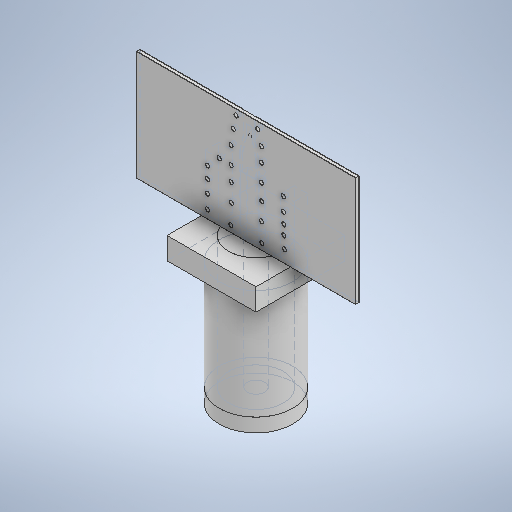
# Autodesk Inventor part: 06_coonector_plus_02mm_res
Saved by Autodesk Inventor 2025.3 (Build 293356000, 356)
## iProperties
Created: 2026-10-17
Part Number: 06_coonector_plus_02mm_res
Material: Generisch
Document SubType Name: Modeling
Designer: v.ivko
Density: 1 g/cm^3
Appearance: Vorgabe
Author: v.ivko
Autodesk Inventor part; units mm, degrees
ref_plane "YZ Plane" through (0, 0, 0) normal (1, 0, 0) x (0, 1, 0)
ref_plane "XZ Plane" through (0, 0, 0) normal (0, 1, 0) x (-1, 0, 0)
ref_plane "XY Plane" through (0, 0, 0) normal (0, 0, 1) x (1, 0, 0)
sketch "Skizze1" plane through (0, 0, 0) normal (0, 0, 1) x (1, 0, 0)
  line L0 (-8, -4) -> (8, -4)
  line L1 (8, -4) -> (8, 4)
  line L2 (8, 4) -> (-8, 4)
  line L3 (-8, 4) -> (-8, -4)
  line L4 (-8, -4) -> (8, 4) construction
  line L5 (8, -4) -> (-8, 4) construction
  point P0 (0, 0)
  dimension "d39" = 16
  dimension "d42" = 8
  constraints: 12 end point, 2 midpoint, 2 parallel, 1 horizontal, 1 perpendicular
  measures "d39" distance between parallel lines of L1 L3
  measures "d42" distance of L0.end L1.end
extrude "Extrusion1" add sketch "Skizze1" along normal blind 0.2
sketch "Skizze2" plane through (-8, -4, 0) normal (0, -1, 0) x (1, 0, 0)
  line L0 (8, 0) -> (8, -43.5363) construction
  line L1 (11.25, 2.75) -> (4.75, 2.75)
  line L2 (4.75, 2.75) -> (4.75, -3.75)
  line L3 (4.75, -3.75) -> (11.25, -3.75)
  line L4 (11.25, -3.75) -> (11.25, 2.75)
  line L5 (11.25, 2.75) -> (4.75, -3.75) construction
  line L6 (4.75, 2.75) -> (11.25, -3.75) construction
  line L7 (0, 0) -> (16, 0) projected
  circle A0 centre (8, -0.5) radius 2
  circle A1 centre (8, -0.5) radius 0.5 construction
  point P0 (11.25, 0)
  point P1 (4.75, 0)
  point P2 (6.0635, 0)
  point P3 (9.9365, 0)
  dimension "d2" = 6.5
  dimension "d3" = 6.5
  dimension "d4" = 0.5
  dimension "d27" = 4
  dimension "d30" = 1
  constraints: 14 end point, 2 centre point, 2 coincident, 2 midpoint, 2 parallel, 1 horizontal, 1 perpendicular, 1 point on line, 1 vertical
  measures "d2" distance of L2.end L3.end
  measures "d3" distance of L1.end L2.end
  measures "d4" distance from line of L7 point (8, -0.5)
  measures "d27" diameter of A0
  measures "d30" diameter of A1
extrude "Extrusion2" add sketch "Skizze2" along normal blind 1.6 separate body contours L4 L7 A0 L2 L1 | L4 L3 L2 L7 A0
sketch "Skizze3" plane through (-8, -5.6, 0) normal (0, -1, 0) x (1, 0, 0)
  circle A0 centre (8, -0.5) radius 2 projected
  circle A1 centre (8, -0.5) radius 2.675
  point P0 (8, 0)
  dimension "d28" = 5.35
  constraints: 1 centre point, 1 coincident
  measures "d28" diameter of A1
extrude "Extrusion3" add sketch "Skizze3" along normal blind 8 bodies 2
sketch "Skizze4" plane through (0, -13.6, -0.5) normal (0, -1, 0) x (1, 0, 0)
  circle A0 centre (0, 0) radius 0.635
  circle A1 centre (0, 0) radius 2 projected
  point P0 (0, 0.5)
  dimension "d29" = 1.27
  constraints: 1 centre point
  measures "d29" diameter of A0
extrude "Extrusion4" add sketch "Skizze4" against normal up to surface (9.6 mm away) separate body
sketch "Skizze5" plane through (0, -13.6, -0.5) normal (0, -1, 0) x (1, 0, 0)
  circle A0 centre (0, 0) radius 0.635
  point P0 (0, 0.5)
  dimension "d31" = 1.27
  constraints: 1 centre point
  measures "d31" diameter of A0
extrude "Extrusion5" add sketch "Skizze5" against normal up to surface (9.6 mm away) separate body
sketch "Skizze6" plane through (0, -4, -0.5) normal (0, 1, 0) x (1, 0, 0)
  circle A0 centre (0, 0) radius 0.635 projected
  circle A1 centre (0, 0) radius 0.475
  point P0 (0, -0.5)
  dimension "d98" = 0.95
  constraints: 1 centre point, 1 coincident
  measures "d98" diameter of A1
extrude "Extrusion6" add sketch "Skizze6" along normal blind 4 contours A1 bodies 4
sketch "Skizze7" plane through (-8, -4, 0) normal (0, 1, 0) x (1, 0, 0)
  line L0 (4.75, 0.035) -> (5.75, 0.035)
  line L1 (5.75, 0.035) -> (5.75, 1.035)
  line L2 (5.75, 1.035) -> (4.75, 1.035)
  line L3 (4.75, 1.035) -> (4.75, 0.035)
  line L4 (4.75, 0.035) -> (5.75, 1.035) construction
  line L5 (5.75, 0.035) -> (4.75, 1.035) construction
  circle A0 centre (8, 0.5) radius 0.635 projected
  line L6 (8, 0.5) -> (8, 3.9078) construction
  line L7 (16, 0) -> (0, 0) projected
  line L8 (4.75, -2.75) -> (4.75, 3.75) projected
  line L9 (11.25, 0.035) -> (10.25, 0.035)
  line L10 (10.25, 0.035) -> (10.25, 1.035)
  line L11 (10.25, 1.035) -> (11.25, 1.035)
  line L12 (11.25, 1.035) -> (11.25, 0.035)
  point P0 (8, 0)
  point P1 (5.25, 0.535)
  dimension "d15" = 1
  dimension "d16" = 1
  dimension "d17" = 0.035
  constraints: 22 end point, 4 symmetric about line, 2 midpoint, 2 parallel, 1 collinear, 1 horizontal, 1 perpendicular, 1 vertical
  measures "d15" distance of L1.end L2.end
  measures "d16" distance of L2.end L0.start
  measures "d17" distance between parallel lines of L7 L0
extrude "Extrusion7" add sketch "Skizze7" along normal blind 4 contours L3 L2 L1 L0 | L9 L10 L11 L12 bodies 2
sketch "Skizze8" plane through (0, 0, 0) normal (0, 0, -1) x (-1, 0, 0)
  line L0 (0.5, 5) -> (-0.5, 5)
  line L1 (-0.5, 5) -> (-0.5, -4)
  line L2 (-0.5, -4) -> (0.5, -4)
  line L3 (0.5, -4) -> (0.5, 5)
  line L4 (0.5, 5) -> (-0.5, -4) construction
  line L5 (-0.5, 5) -> (0.5, -4) construction
  line L6 (8, -4) -> (-8, -4) projected
  line L7 (8, 4) -> (8, -4) projected
  line L8 (-8, -4) -> (-8, 4) projected
  line L9 (0, 0) -> (0, -24.5211) construction
  line L10 (0, 0.5) -> (0, -4) construction
  line L11 (-0.9, -4) -> (-8, -4)
  line L12 (-8, -4) -> (-8, 4)
  line L13 (-8, 4) -> (-0.9, 4)
  line L14 (-0.9, 4) -> (-0.9, -4)
  line L15 (0.9, -4) -> (8, -4)
  line L16 (8, -4) -> (8, 4)
  line L17 (8, 4) -> (0.9, 4)
  line L18 (0.9, 4) -> (0.9, -4)
  line L19 (-0.2141, 6.419) -> (0.2141, 2.4267) construction
  line L20 (0.2141, 6.419) -> (-0.2141, 2.4267) construction
  line L21 (-0.2141, 2.4267) -> (-0.5, 1.2)
  line L22 (0.2141, 2.4267) -> (0.5, 1.2)
  line L23 (-8, 4) -> (8, 4) projected
  line L24 (-0.7317, 4) -> (1.4375, 4)
  line L25 (0.2141, 4) -> (0.2141, 2.4267)
  line L26 (-0.2141, 2.4267) -> (-0.2141, 4)
  line L27 (-0.6947, 1.2456) -> (-0.4141, 2.4497)
  line L28 (-0.4141, 2.4497) -> (-0.4141, 4)
  line L29 (0.6947, 1.2456) -> (0.4141, 2.4497)
  line L30 (0.4141, 2.4497) -> (0.4141, 4)
  line L31 (-0.6947, 1.2456) -> (-0.6947, -4)
  line L32 (0.6947, 1.2456) -> (0.6947, -4)
  line L33 (-2.4088, 4) -> (2.1688, 4)
  line L34 (-0.2141, 2.4267) -> (-0.2141, 0.5561) construction
  line L35 (0.2141, 2.4267) -> (0.2141, 0.5909) construction
  line L36 (0.5, 0) -> (-0.5, 0) projected
  line L37 (-0.2141, 2.4031) -> (2.2577, 2.4031) construction
  line L38 (-0.2141, 3.194) -> (0.2141, 3.194)
  point P0 (-0.9, -4)
  point P1 (0, 4.4228)
  point P2 (0.5, 1.2)
  point P3 (-0.5, -4)
  point P4 (-0.5, 4)
  point P5 (0.5, 4)
  point P6 (0.5, 2.0811)
  point P7 (-0.5, 2.0811)
  point P8 (-0.2141, 4)
  point P9 (0.2141, 4)
  point P10 (0.4141, 4)
  point P11 (-0.4141, 4)
  dimension "d20" = 1
  dimension "d21" = 9
  dimension "d81" = 0.2
  dimension "d82" = 0.2
  dimension "d97" = 1.2
  constraints: 68 end point, 14 point on line, 7 parallel, 6 perpendicular, 5 midpoint, 4 vertical, 3 collinear, 3 horizontal, 2 symmetric about line, 2 other
  measures "d20" distance between parallel lines of L1 L3
  measures "d21" distance of L0.end L1.end
  measures "d81" distance between parallel lines of L21 L27
  measures "d82" distance between parallel lines of L22 L29
  measures "d97" distance from line of L36 L21.end
extrude "Extrusion8" add sketch "Skizze8" along normal blind 0.035 separate body contours L23 L18 L6 L32 L29 L3 | L3 L29 L30 L23 | L23 L28 L27 L1 | L1 L27 L31 L6 L14 L23 | L17 L7 L6 L18 | L3 L36 L1 L21 L26 L38 L25 L22 | L14 L6 L8 L13
sketch "Skizze9" plane through (0, 0, 0.2) normal (0, 0, 1) x (1, 0, 0)
  line L0 (8, -4) -> (8, 4) projected
  line L1 (8, 4) -> (-8, 4) projected
  line L2 (-8, 4) -> (-8, -4) projected
  line L3 (-8, -4) -> (8, -4) projected
  point P0 (0, 0)
extrude "Extrusion9" add sketch "Skizze9" along normal blind 0.035 separate body
sketch "Skizze10" plane through (0, 0, -0.5) normal (0, 1, 0) x (1, 0, 0)
  circle A0 centre (0, 0) radius 0.635 projected
  line L0 (0.5, -0.465) -> (-0.5, -0.465) projected
  line L1 (-0.635, 0) -> (0.635, 0)
  line L2 (0.635, 0) -> (0.635, -0.465)
  line L3 (0.635, -0.465) -> (-0.635, -0.465)
  line L4 (-0.635, -0.465) -> (-0.635, 0)
  line L5 (0.635, 0) -> (0.635, 0.1708) construction
  point P0 (0, -0.5)
  point P1 (-0.5, -0.465)
  constraints: 10 end point, 2 parallel, 2 vertical, 1 collinear, 1 horizontal, 1 perpendicular, 1 point on line, 3 other
extrude "Extrusion10" add sketch "Skizze10" against normal blind 3.5 separate body contours L2 L3 L0 A0 | A0 L0 L1 | A0 L0 L3 L4
sketch "Skizze11" plane through (0, -13.6, -0.5) normal (0, -1, 0) x (1, 0, 0)
  line L0 (-0.635, 0) -> (0.635, 0) projected
  circle A0 centre (0, 0) radius 2.675
  point P0 (0, 0.5)
  constraints: 1 centre point, 1 midpoint
extrude "Extrusion11" add sketch "Skizze11" along normal blind 1 separate body
sketch "Skizze13" plane through (0, 0, -0.035) normal (0, 0, -1) x (-1, 0, 0)
  circle A0 centre (-2.736, -0.7726) radius 0.15
  circle A1 centre (-2.7639, -2.2491) radius 0.15
  circle A2 centre (-2.7639, -1.5526) radius 0.15
  circle A3 centre (-2.8057, -3.1127) radius 0.15
  circle A4 centre (2.8076, -0.6226) radius 0.15
  circle A5 centre (2.8215, -2.3991) radius 0.15
  circle A6 centre (2.8215, -1.483) radius 0.15
  circle A7 centre (2.8215, -3.4052) radius 0.15
  circle A8 centre (-1.1162, 0.268) radius 0.15
  circle A9 centre (1.0869, 0.268) radius 0.15
  circle A10 centre (-1.1162, 1.5331) radius 0.15
  circle A11 centre (-1.1162, 2.5668) radius 0.15
  circle A12 centre (1.0956, 1.5331) radius 0.15
  circle A13 centre (0.9369, 2.6407) radius 0.15
  circle A14 centre (-0.8558, 3.5159) radius 0.15
  circle A15 centre (0.726, 3.5897) radius 0.15
  circle A16 centre (-2.7223, 0.2047) radius 0.15
  circle A17 centre (1.9598, 0.268) radius 0.15
  circle A18 centre (-1.1405, -0.9026) radius 0.15
  circle A19 centre (-1.1241, -2.1787) radius 0.15
  circle A20 centre (-1.1487, -3.5296) radius 0.15
  circle A21 centre (1.0864, -0.8033) radius 0.15
  circle A22 centre (1.0741, -2.105) radius 0.15
  circle A23 centre (1.0987, -3.5296) radius 0.15
  dimension "d45" = 0.3
  dimension "d46" = 0.3
  dimension "d47" = 0.3
  dimension "d48" = 0.3
  dimension "d49" = 0.3
  dimension "d50" = 0.3
  dimension "d51" = 0.3
  dimension "d52" = 0.3
  dimension "d53" = 0.3
  dimension "d61" = 0.3
  dimension "d83" = 0.3
  dimension "d84" = 0.3
  dimension "d85" = 0.3
  dimension "d86" = 0.3
  dimension "d87" = 0.3
  dimension "d88" = 0.3
  dimension "d89" = 0.3
  dimension "d90" = 0.3
  dimension "d91" = 0.3
  dimension "d92" = 0.3
  dimension "d93" = 0.3
  dimension "d94" = 0.3
  dimension "d95" = 0.3
  dimension "d96" = 0.3
  constraints: 24 centre point
  measures "d45" diameter of A0
  measures "d46" diameter of A1
  measures "d47" diameter of A2
  measures "d48" diameter of A3
  measures "d49" diameter of A4
  measures "d50" diameter of A5
  measures "d51" diameter of A6
  measures "d52" diameter of A7
  measures "d53" diameter of A8
  measures "d61" diameter of A9
  measures "d83" diameter of A10
  measures "d84" diameter of A11
  measures "d85" diameter of A12
  measures "d86" diameter of A13
  measures "d87" diameter of A14
  measures "d88" diameter of A15
  measures "d89" diameter of A16
  measures "d90" diameter of A17
  measures "d91" diameter of A18
  measures "d92" diameter of A19
  measures "d93" diameter of A20
  measures "d94" diameter of A21
  measures "d95" diameter of A22
  measures "d96" diameter of A23
extrude "Extrusion13" cut sketch "Skizze13" against normal blind 10 bodies 5 1 6
sketch "Skizze17" plane through (0.2141, -4.7177, 0) normal (1, 0, 0) x (0, 0, -1)
  circle A0 centre (0.0175, 7.5546) radius 0.25
  line L0 (0.035, 7) -> (0, 7) projected
  line L1 (0.0175, 7) -> (0.0175, 6.5049) construction
  point P0 (0, 4.7177)
  dimension "d77" = 0.5
  constraints: 2 end point, 1 centre point, 1 midpoint, 1 point on line, 1 vertical
  measures "d77" diameter of A0
extrude "Extrusion17" add sketch "Skizze17" along normal up to surface (0.2 mm away) separate body
